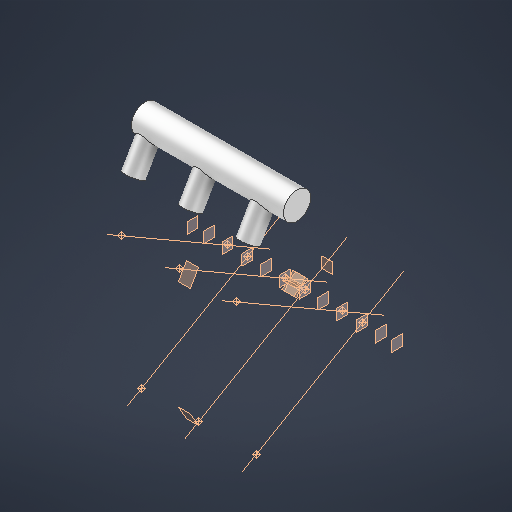
# Autodesk Inventor part: Exhaust_Manifold_A_SIMPLIFIED
Saved by Autodesk Inventor 2027.1 (Build 311270010, 270A)
## iProperties
Created: 2026-10-17
Part Number: Exhaust_Manifold_A_SIMPLIFIED
Material: Stainless Steel AISI 304
Document SubType Name: Modeling
Designer: kashyap
Density: 8 g/cm^3
Appearance: Chrome - Satin
Mass: 4414.24 g
Surface Area: 845.73 cm^2
Volume: 551.78 cm^3
Material_Status: Assumed for this reconstruction
Author: kashyap
Autodesk Inventor part; units mm, degrees
ref_plane "XZ Plane" through (0, 0, 0) normal (0, 1, 0) x (-1, 0, 0)
derived "V6_Engine_Master.ipt"
ref_plane "Bank_A_Plane" through (0, 0, 0) normal (0, 0.8660254, -0.5) x (-1, 0, 0)
ref_plane "Bank_B_Plane" through (0, 0, 0) normal (0, 0.8660254, 0.5) x (-1, 0, 0)
ref_plane "Bank_A_Perp_Plane" through (0, 0, 0) normal (0, 0.5, 0.8660254) x (-1, 0, 0)
ref_plane "Bank_B_Perp_Plane" through (0, 0, 0) normal (0, -0.5, 0.8660254) x (-1, 0, 0)
ref_plane "Bank_A_Deck_Plane" through (0, 112.9, 195.5485) normal (0, 0.5, 0.8660254) x (-1, 0, 0)
ref_plane "Bank_B_Deck_Plane" through (0, -112.9, 195.5485) normal (0, -0.5, 0.8660254) x (-1, 0, 0)
ref_plane "Cyl_A1_Station_Plane" through (-123.8, 0, 0) normal (1, 0, 0) x (0, 1, 0)
ref_plane "Cyl_A2_Station_Plane" through (-18.3, 0, 0) normal (1, 0, 0) x (0, 1, 0)
ref_plane "Cyl_A3_Station_Plane" through (87.2, 0, 0) normal (1, 0, 0) x (0, 1, 0)
ref_plane "Cyl_B1_Station_Plane" through (-87.2, 0, 0) normal (1, 0, 0) x (0, 1, 0)
ref_plane "Cyl_B2_Station_Plane" through (18.3, 0, 0) normal (1, 0, 0) x (0, 1, 0)
ref_plane "Cyl_B3_Station_Plane" through (123.8, 0, 0) normal (1, 0, 0) x (0, 1, 0)
ref_plane "Main_Bearing_Station_1" through (-158.25, 0, 0) normal (1, 0, 0) x (0, 1, 0)
ref_plane "Main_Bearing_Station_2" through (-52.75, 0, 0) normal (1, 0, 0) x (0, 1, 0)
ref_plane "Main_Bearing_Station_3" through (52.75, 0, 0) normal (1, 0, 0) x (0, 1, 0)
ref_plane "Main_Bearing_Station_4" through (158.25, 0, 0) normal (1, 0, 0) x (0, 1, 0)
ref_plane "Front_Interface" through (-188.25, 0, 0) normal (1, 0, 0) x (0, 1, 0)
ref_plane "Rear_Interface" through (188.25, 0, 0) normal (1, 0, 0) x (0, 1, 0)
ref_plane "Oil_Pan_Plane" through (0, 0, -60) normal (0, 0, 1) x (1, 0, 0)
ref_plane "Exhaust_Face_Plane" through (0, 73.6122, -42.5) normal (0, 0.8660254, -0.5) x (-1, 0, 0)
sketch "SK_Runners" plane through (0, 73.6122, -42.5) normal (0, 0.8660254, -0.5) x (-1, 0, 0)
  circle A0 centre (123.8, 248.9693) radius 17
  circle A1 centre (18.3, 248.9693) radius 17
  circle A2 centre (-87.2, 248.9693) radius 17
  dimension "d20" = 34
  dimension "d21" = 34
  dimension "d22" = 34
  constraints: 3 centre point
  measures "d20" diameter of A0
  measures "d21" diameter of A1
  measures "d22" diameter of A2
extrude "Runners" add sketch "SK_Runners" along normal blind 75
ref_plane "Collector_Start_Plane" through (-140, 0, 0) normal (1, 0, 0) x (0, 1, 0)
sketch "SK_Collector" plane through (-140, 0, 0) normal (1, 0, 0) x (0, 1, 0)
  circle A0 centre (263.0487, 135.6137) radius 25
  dimension "d26" = 50
  constraints: 1 centre point
  measures "d26" diameter of A0
extrude "Collector_SIMPLIFIED" add sketch "SK_Collector" along normal blind 280
sketch "SK_Runner_Bores" plane through (0, 73.6122, -42.5) normal (0, 0.8660254, -0.5) x (-1, 0, 0)
  circle A0 centre (123.8, 248.9693) radius 14
  circle A1 centre (18.3, 248.9693) radius 14
  circle A2 centre (-87.2, 248.9693) radius 14
  dimension "d29" = 28
  dimension "d30" = 28
  dimension "d31" = 28
  constraints: 3 centre point
  measures "d29" diameter of A0
  measures "d30" diameter of A1
  measures "d31" diameter of A2
extrude "Runner_Bores" cut sketch "SK_Runner_Bores" along normal blind 75
equation "\"d23\" = Exhaust_Runner_Length + 0.5 * Exhaust_Collector_Dia"
equation "\"d26\" = Exhaust_Collector_Dia"
equation "\"d27\" = 2 * Exhaust_Collector_Half_Length"
equation "\"d29\" = Exhaust_Port_Dia"
equation "\"d30\" = Exhaust_Port_Dia"
equation "\"d31\" = Exhaust_Port_Dia"
equation "\"d32\" = Exhaust_Runner_Length + 0.5 * Exhaust_Collector_Dia"
equation "\"Exhaust_Runner_Length\" = 50"
equation "\"Exhaust_Collector_Dia\" = 50"
equation "\"Exhaust_Collector_Half_Length\" = 140"
equation "\"Exhaust_Port_Dia\" = 28"
body "Solid1"
